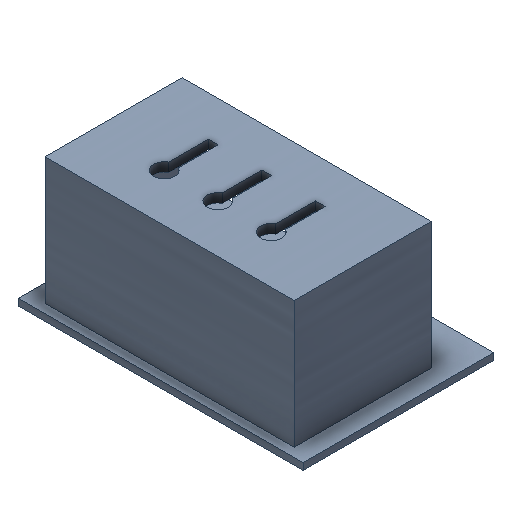
# Autodesk Inventor part: OT2-Pipette V0.3 - tip stripper
Saved by Autodesk Inventor 2025.5 (Build 295498000, 498)
## iProperties
Created: 2026-11-01
Part Number: OT2-Pipette V0.3 - tip stripper
Material: Generisch
Description: printed deck-slot tip stripper (SBS footprint, 3 entry holes + slots)
Document SubType Name: Modeling
Designer: benir
Density: 1 g/cm^3
Appearance: Light Steel Blue
Author: benir
Autodesk Inventor part; units mm, degrees
ref_plane "y=st_base_t" through (0, 3, 0) normal (0, 1, 0) x (-1, 0, 0)
sketch "base plate" plane through (0, 3, 0) normal (0, 1, 0) x (-1, 0, 0)
  line L0 (0, 0) -> (-127.76, 0)
  line L1 (-127.76, 0) -> (-127.76, 85.48)
  line L2 (-127.76, 85.48) -> (0, 85.48)
  line L3 (0, 85.48) -> (0, 0)
  line L4 (0, -17.096) -> (0, 102.576) projected
  line L5 (25.552, 0) -> (-153.312, 0) projected
  dimension "d3" = 127.76
  dimension "d4" = 85.48
  constraints: 8 end point, 2 collinear, 2 parallel, 1 horizontal, 1 perpendicular
  measures "d3" distance of L0.start L0.end
  measures "d4" distance of L2.end L0.start
extrude "Extrusion2" add sketch "base plate" against normal blind 3
sketch "side wall 1" plane through (0, 3, 0) normal (0, 1, 0) x (-1, 0, 0)
  line L0 (-8, 20) -> (-14, 20)
  line L1 (-14, 20) -> (-14, 81.48)
  line L2 (-14, 81.48) -> (-8, 81.48)
  line L3 (-8, 81.48) -> (-8, 20)
  line L4 (0, -17.096) -> (0, 102.576) projected
  line L5 (25.552, 0) -> (-153.312, 0) projected
  point P0 (0, 0)
  dimension "d7" = 6
  dimension "d8" = 61.48
  dimension "d9" = 8
  dimension "d10" = 20
  constraints: 8 end point, 2 parallel, 1 horizontal, 1 perpendicular
  measures "d7" distance of L0.start L0.end
  measures "d8" distance of L2.end L0.start
  measures "d9" horizontal distance of point (0, 0) L2.end
  measures "d10" vertical distance of point (0, 0) L0.start
extrude "Extrusion3" add sketch "side wall 1" along normal blind 57
sketch "side wall 2" plane through (0, 3, 0) normal (0, 1, 0) x (-1, 0, 0)
  line L0 (-113.76, 20) -> (-119.76, 20)
  line L1 (-119.76, 20) -> (-119.76, 81.48)
  line L2 (-119.76, 81.48) -> (-113.76, 81.48)
  line L3 (-113.76, 81.48) -> (-113.76, 20)
  line L4 (0, -17.096) -> (0, 102.576) projected
  line L5 (25.552, 0) -> (-153.312, 0) projected
  point P0 (0, 0)
  dimension "d13" = 6
  dimension "d14" = 61.48
  dimension "d15" = 113.76
  dimension "d16" = 20
  constraints: 8 end point, 2 parallel, 1 horizontal, 1 perpendicular
  measures "d13" distance of L0.start L0.end
  measures "d14" distance of L2.end L0.start
  measures "d15" horizontal distance of point (0, 0) L2.end
  measures "d16" vertical distance of point (0, 0) L0.start
extrude "Extrusion4" add sketch "side wall 2" along normal blind 57
ref_plane "y=st_h - st_plate_t" through (0, 56, 0) normal (0, 1, 0) x (-1, 0, 0)
sketch "top plate" plane through (0, 56, 0) normal (0, 1, 0) x (-1, 0, 0)
  line L0 (-8, 20) -> (-119.76, 20)
  line L1 (-119.76, 20) -> (-119.76, 81.48)
  line L2 (-119.76, 81.48) -> (-8, 81.48)
  line L3 (-8, 81.48) -> (-8, 20)
  line L4 (0, -17.096) -> (0, 102.576) projected
  line L5 (25.552, 0) -> (-153.312, 0) projected
  point P0 (0, 0)
  dimension "d20" = 111.76
  dimension "d21" = 61.48
  dimension "d22" = 8
  dimension "d23" = 20
  constraints: 8 end point, 2 parallel, 1 horizontal, 1 perpendicular
  measures "d20" distance of L0.start L0.end
  measures "d21" distance of L2.end L0.start
  measures "d22" horizontal distance of point (0, 0) L2.end
  measures "d23" vertical distance of point (0, 0) L0.start
extrude "Extrusion5" add sketch "top plate" along normal blind 4
sketch "back wall" plane through (0, 3, 0) normal (0, 1, 0) x (-1, 0, 0)
  line L0 (-8, 78.48) -> (-119.76, 78.48)
  line L1 (-119.76, 78.48) -> (-119.76, 81.48)
  line L2 (-119.76, 81.48) -> (-8, 81.48)
  line L3 (-8, 81.48) -> (-8, 78.48)
  line L4 (0, -17.096) -> (0, 102.576) projected
  line L5 (25.552, 0) -> (-153.312, 0) projected
  point P0 (0, 0)
  dimension "d26" = 111.76
  dimension "d27" = 3
  dimension "d28" = 8
  dimension "d29" = 78.48
  constraints: 8 end point, 2 parallel, 1 horizontal, 1 perpendicular
  measures "d26" distance of L0.start L0.end
  measures "d27" distance of L2.end L0.start
  measures "d28" horizontal distance of point (0, 0) L2.end
  measures "d29" vertical distance of point (0, 0) L0.start
extrude "Extrusion6" add sketch "back wall" along normal blind 57
ref_plane "y=st_h - st_plate_t - cut_over" through (0, 55, 0) normal (0, 1, 0) x (-1, 0, 0)
sketch "entry holes" plane through (0, 55, 0) normal (0, 1, 0) x (-1, 0, 0)
  circle A0 centre (-40, 60) radius 4.75
  circle A1 centre (-64, 60) radius 4.75
  circle A2 centre (-88, 60) radius 4.75
  point P0 (0, 0)
  dimension "d33" = 60
  dimension "d34" = 40
  dimension "d35" = 9.5
  dimension "d36" = 60
  dimension "d37" = 64
  dimension "d38" = 9.5
  dimension "d39" = 60
  dimension "d40" = 88
  dimension "d41" = 9.5
  constraints: 3 centre point
  measures "d33" vertical distance of point (0, 0) A0.centre
  measures "d34" horizontal distance of point (0, 0) A0.centre
  measures "d35" diameter of A0
  measures "d36" vertical distance of point (0, 0) A1.centre
  measures "d37" horizontal distance of point (0, 0) A1.centre
  measures "d38" diameter of A1
  measures "d39" vertical distance of point (0, 0) A2.centre
  measures "d40" horizontal distance of point (0, 0) A2.centre
  measures "d41" diameter of A2
extrude "Extrusion7" cut sketch "entry holes" along normal blind 6
sketch "stripper slots" plane through (0, 55, 0) normal (0, 1, 0) x (-1, 0, 0)
  line L0 (-37.8, 38) -> (-42.2, 38)
  line L1 (-42.2, 38) -> (-42.2, 60)
  line L2 (-42.2, 60) -> (-37.8, 60)
  line L3 (-37.8, 60) -> (-37.8, 38)
  line L4 (0, -17.096) -> (0, 102.576) projected
  line L5 (25.552, 0) -> (-153.312, 0) projected
  line L6 (-61.8, 38) -> (-66.2, 38)
  line L7 (-66.2, 38) -> (-66.2, 60)
  line L8 (-66.2, 60) -> (-61.8, 60)
  line L9 (-61.8, 60) -> (-61.8, 38)
  line L10 (-85.8, 38) -> (-90.2, 38)
  line L11 (-90.2, 38) -> (-90.2, 60)
  line L12 (-90.2, 60) -> (-85.8, 60)
  line L13 (-85.8, 60) -> (-85.8, 38)
  point P0 (0, 0)
  dimension "d44" = 4.4
  dimension "d45" = 22
  dimension "d46" = 37.8
  dimension "d47" = 38
  dimension "d48" = 4.4
  dimension "d49" = 22
  dimension "d50" = 61.8
  dimension "d51" = 38
  dimension "d52" = 4.4
  dimension "d53" = 22
  dimension "d54" = 85.8
  dimension "d55" = 38
  constraints: 24 end point, 6 parallel, 3 horizontal, 3 perpendicular
  measures "d44" distance of L0.start L0.end
  measures "d45" distance of L2.end L0.start
  measures "d46" horizontal distance of point (0, 0) L2.end
  measures "d47" vertical distance of point (0, 0) L0.start
  measures "d48" distance of L6.start L6.end
  measures "d49" distance of L8.end L6.start
  measures "d50" horizontal distance of point (0, 0) L8.end
  measures "d51" vertical distance of point (0, 0) L6.start
  measures "d52" distance of L10.start L10.end
  measures "d53" distance of L12.end L10.start
  measures "d54" horizontal distance of point (0, 0) L12.end
  measures "d55" vertical distance of point (0, 0) L10.start
extrude "Extrusion8" cut sketch "stripper slots" along normal blind 6
equation "\"d3\" = st_w"
equation "\"d4\" = st_d"
equation "\"d5\" = st_base_t"
equation "\"d7\" = st_side_w + 0 * st_side_x"
equation "\"d8\" = -st_back + st_d - st_front"
equation "\"d9\" = st_side_x"
equation "\"d10\" = st_front"
equation "\"d11\" = st_h - st_base_t"
equation "\"d13\" = 0 * st_side_x + 0 * st_w + st_side_w"
equation "\"d14\" = -st_back + st_d - st_front"
equation "\"d15\" = -st_side_x + st_w - st_side_w"
equation "\"d16\" = st_front"
equation "\"d17\" = st_h - st_base_t"
equation "\"d20\" = -2 * st_side_x + st_w"
equation "\"d21\" = -st_back + st_d - st_front"
equation "\"d22\" = st_side_x"
equation "\"d23\" = st_front"
equation "\"d24\" = st_plate_t"
equation "\"d26\" = -2 * st_side_x + st_w"
equation "\"d27\" = 0 * st_back + 0 * st_d + st_back_t"
equation "\"d28\" = st_side_x"
equation "\"d29\" = -st_back + st_d - st_back_t"
equation "\"d30\" = st_h - st_base_t"
equation "\"d33\" = st_entry_z"
equation "\"d34\" = st_x1"
equation "\"d35\" = st_entry_d"
equation "\"d36\" = st_entry_z"
equation "\"d37\" = st_x2"
equation "\"d38\" = st_entry_d"
equation "\"d39\" = st_entry_z"
equation "\"d40\" = st_x3"
equation "\"d41\" = st_entry_d"
equation "\"d42\" = st_plate_t + 2 * cut_over"
equation "\"d44\" = st_slot_w + 0 * st_x1"
equation "\"d45\" = 0 * st_entry_z + st_slot_len"
equation "\"d46\" = st_x1 - 0.5 * st_slot_w"
equation "\"d47\" = st_entry_z - st_slot_len"
equation "\"d48\" = st_slot_w + 0 * st_x2"
equation "\"d49\" = 0 * st_entry_z + st_slot_len"
equation "\"d50\" = st_x2 - 0.5 * st_slot_w"
equation "\"d51\" = st_entry_z - st_slot_len"
equation "\"d52\" = st_slot_w + 0 * st_x3"
equation "\"d53\" = 0 * st_entry_z + st_slot_len"
equation "\"d54\" = st_x3 - 0.5 * st_slot_w"
equation "\"d55\" = st_entry_z - st_slot_len"
equation "\"d56\" = st_plate_t + 2 * cut_over"
equation "\"st_w\" = 127.76"
equation "\"st_d\" = 85.48"
equation "\"st_base_t\" = 3"
equation "\"st_side_w\" = 6"
equation "\"st_side_x\" = 8"
equation "\"st_back\" = 4"
equation "\"st_front\" = 20"
equation "\"st_h\" = 60"
equation "\"st_plate_t\" = 4"
equation "\"st_back_t\" = 3"
equation "\"st_entry_d\" = 9.5"
equation "\"cut_over\" = 1"
equation "\"st_slot_w\" = 4.4"
equation "\"st_x1\" = 40"
equation "\"st_entry_z\" = 60"
equation "\"st_slot_len\" = 22"
equation "\"st_x2\" = 64"
equation "\"st_x3\" = 88"
body "Solid2"
